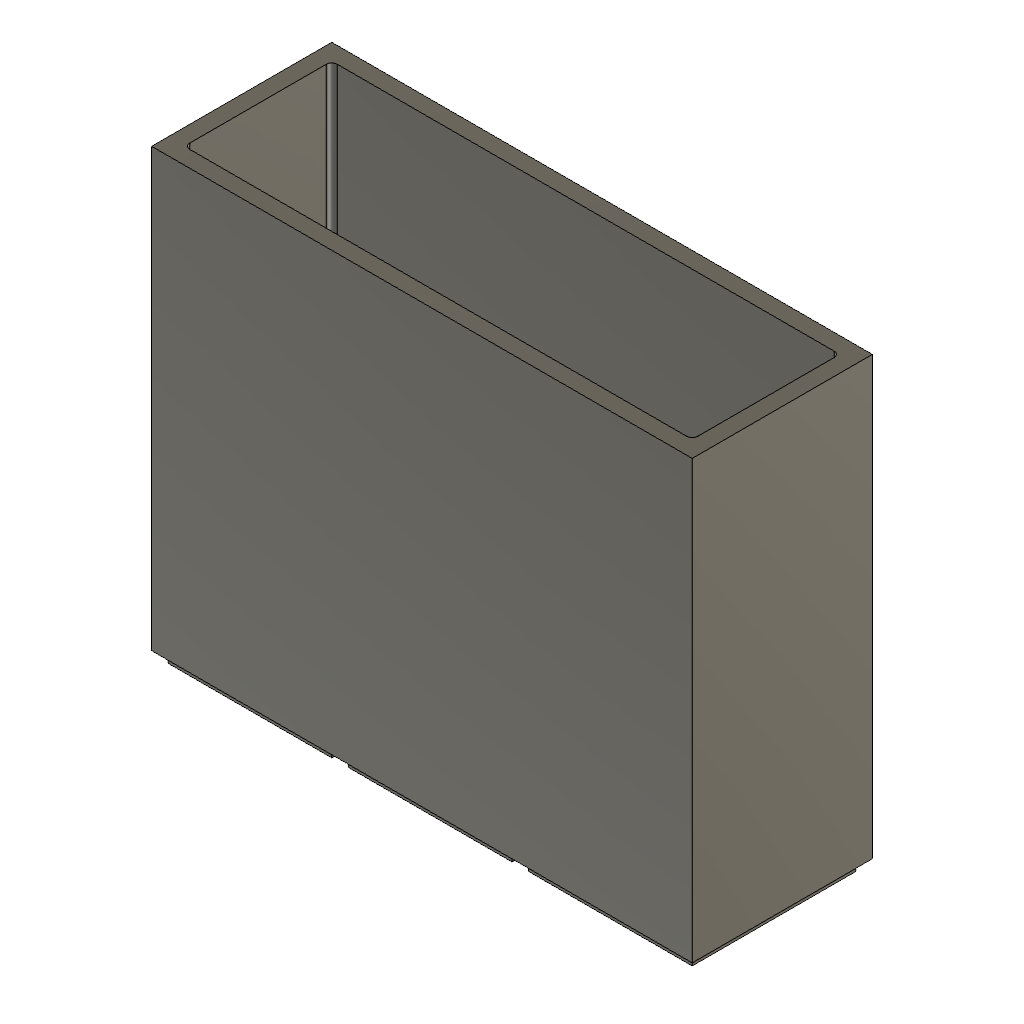
Miscellaneous Compartment (Autodesk Fusion 360 design; units mm, degrees)
part number: 2026-10-19-01-39-08-296
Autodesk Fusion 360 part; units mm, degrees
sketch "Sketch1" plane through (0, 0, 0) normal (0, 0, 1) x (1, 0, 0)
  line L0 (-63.6283, 27.1118) -> (35.3717, 27.1118)
  line L1 (35.3717, 27.1118) -> (35.3717, -5.8882)
  line L2 (35.3717, -5.8882) -> (-63.6283, -5.8882)
  line L3 (-63.6283, -5.8882) -> (-63.6283, 27.1118)
  line L4 (-60.6283, 24.1118) -> (32.3717, 24.1118)
  line L5 (32.3717, 24.1118) -> (32.3717, -2.8882)
  line L6 (32.3717, -2.8882) -> (-60.6283, -2.8882)
  line L7 (-60.6283, -2.8882) -> (-60.6283, 24.1118)
  dimension "d1" = 33
  dimension "d2" = 99
  dimension "d3" = 3
  dimension "d4" = 3
  dimension "d5" = 3
  dimension "d6" = 3
  constraint horizontal L0
  constraint vertical L1
  constraint horizontal L2
  constraint vertical L3
  constraint horizontal L4
  constraint vertical L5
  constraint horizontal L6
  constraint vertical L7
  measures "d1" distance of L0 L2
  measures "d2" distance of L1 L3
  measures "d3" distance of L0 L4
  measures "d4" distance of L3 L7
  measures "d5" distance of L2 L6
  measures "d6" distance of L1 L5
extrude "Extrude1" add sketch "Sketch1" along normal blind 80
sketch "Sketch2" plane through (0, 0, 0) normal (0, 0, 1) x (1, 0, 0)
  line L0 (-63.6283, -5.8881) -> (35.3717, -5.8881)
  line L1 (35.3717, -5.8881) -> (35.3717, 27.1118)
  line L2 (35.3717, 27.1118) -> (-63.6283, 27.1118)
  line L3 (-63.6283, 27.1118) -> (-63.6283, -5.8881)
  constraint horizontal L0
  constraint vertical L1
  constraint horizontal L2
  constraint vertical L3
extrude "Extrude2" add sketch "Sketch2" along normal blind 3
sketch "Sketch3" plane through (0, 0, 0) normal (0, 0, -1) x (1, 0, 0)
  line L0 (35.3717, 5.8882) -> (-63.6283, 5.8882)
  line L1 (-63.6283, 5.8882) -> (-63.6283, -27.1118)
  line L2 (-63.6283, -27.1118) -> (35.3717, -27.1118)
  line L3 (35.3717, -27.1118) -> (35.3717, 5.8882)
  line L4 (-63.6283, 5.8882) -> (35.3717, 5.8882)
  line L5 (35.3717, 5.8882) -> (35.3717, -27.1118)
  line L6 (35.3717, -27.1118) -> (-63.6283, -27.1118)
  line L7 (-63.6283, -27.1118) -> (-63.6283, 5.8882)
  line L8 (-62.1283, 4.3882) -> (-32.1283, 4.3882)
  line L9 (-32.1283, 4.3882) -> (-32.1283, -25.6118)
  line L10 (-32.1283, -25.6118) -> (-62.1283, -25.6118)
  line L11 (-62.1283, -25.6118) -> (-62.1283, 4.3882)
  line L12 (-29.1283, 4.3882) -> (0.8717, 4.3882)
  line L13 (0.8717, 4.3882) -> (0.8717, -25.6118)
  line L14 (0.8717, -25.6118) -> (-29.1283, -25.6118)
  line L15 (-29.1283, -25.6118) -> (-29.1283, 4.3882)
  line L16 (3.8717, 4.3882) -> (33.8717, 4.3882)
  line L17 (33.8717, 4.3882) -> (33.8717, -25.6118)
  line L18 (33.8717, -25.6118) -> (3.8717, -25.6118)
  line L19 (3.8717, -25.6118) -> (3.8717, 4.3882)
  dimension "d11" = 1.5
  dimension "d12" = 1.5
  dimension "d13" = 1.5
  dimension "d14" = 1.5
  dimension "d15" = 1.5
  dimension "d16" = 1.5
  dimension "d17" = 1.5
  dimension "d18" = 1.5
  dimension "d19" = 3
  dimension "d20" = 3
  dimension "d21" = 30
  dimension "d22" = 30
  constraint horizontal L4
  constraint vertical L5
  constraint horizontal L6
  constraint vertical L7
  constraint coincident L2.end L3.start
  constraint coincident L0.end L1.start
  constraint horizontal L8
  constraint vertical L9
  constraint horizontal L10
  constraint vertical L11
  constraint horizontal L12
  constraint vertical L13
  constraint horizontal L14
  constraint vertical L15
  constraint horizontal L16
  constraint vertical L17
  constraint horizontal L18
  constraint vertical L19
  measures "d11" distance of L7 L11
  measures "d12" distance of L4 L8
  measures "d13" distance of L6 L10
  measures "d14" distance of L4 L12
  measures "d15" distance of L6 L14
  measures "d16" distance of L4 L16
  measures "d17" distance of L6 L18
  measures "d18" distance of L5 L17
  measures "d19" distance of L9 L15
  measures "d20" distance of L13 L19
  measures "d21" distance of L9 L11
  measures "d22" distance of L13 L15
extrude "Extrude3" add sketch "Sketch3" along normal blind 3 contours L8 L9 L10 L11 | L12 L13 L14 L15 | L16 L17 L18 L19
chamfer "Chamfer1" distance 1 angle 45 3 faces at (-52.1283, 5.6118, -3) (-19.1283, 5.6118, -3) (13.8717, 5.6118, -3) tangent chain off
fillet "Fillet1" radius 1 1 edges at (-60.6283, 24.1118, 41.5)
fillet "Fillet2" radius 1 1 edges at (-60.6283, -2.8882, 41.5)
fillet "Fillet3" radius 1 1 edges at (32.3717, -2.8882, 41.5)
fillet "Fillet4" radius 1 1 edges at (32.3717, 24.1118, 41.5)
